Autodesk Fusion 360 part; units mm, degrees
(part 2 of 2)
sketch "Editable cross section (97)" plane through (0, 0, 0) normal (0, 0, 1) x (1, 0, 0) in component "left scoring bearing bridge -33"
  line L0 (-7.5, -5) -> (7.5, -5)
  line L1 (7.5, -5) -> (7.5, 5)
  line L2 (7.5, 5) -> (-7.5, 5)
  line L3 (-7.5, 5) -> (-7.5, -5)
extrude "Stock length''''''''''''''''''''''''''''''''''''''''''''''''''''''''''''''''''''''''''''''''''''''''''''''''" add sketch "Editable cross section (97)" along normal blind 42 separate body makes body 97 in component "left scoring bearing bridge -33"
sketch "Editable cross section (98)" plane through (0, 0, 0) normal (0, 0, 1) x (1, 0, 0) in component "left scoring bearing bridge 33"
  line L0 (-7.5, -5) -> (7.5, -5)
  line L1 (7.5, -5) -> (7.5, 5)
  line L2 (7.5, 5) -> (-7.5, 5)
  line L3 (-7.5, 5) -> (-7.5, -5)
extrude "Stock length'''''''''''''''''''''''''''''''''''''''''''''''''''''''''''''''''''''''''''''''''''''''''''''''''" add sketch "Editable cross section (98)" along normal blind 42 separate body makes body 98 in component "left scoring bearing bridge 33"
sketch "Editable cross section (99)" plane through (0, 0, 0) normal (0, 0, 1) x (1, 0, 0) in component "left feed diverter pivot"
  circle A0 centre (0, 0) radius 7
extrude "Stock length''''''''''''''''''''''''''''''''''''''''''''''''''''''''''''''''''''''''''''''''''''''''''''''''''" add sketch "Editable cross section (99)" along normal blind 24 separate body makes body 99 in component "left feed diverter pivot"
sketch "Editable cross section (100)" plane through (0, 0, 0) normal (0, 0, 1) x (1, 0, 0) in component "right feed diverter pivot"
  circle A0 centre (0, 0) radius 7
extrude "Stock length'''''''''''''''''''''''''''''''''''''''''''''''''''''''''''''''''''''''''''''''''''''''''''''''''''" add sketch "Editable cross section (100)" along normal blind 24 separate body makes body 100 in component "right feed diverter pivot"
sketch "Editable cross section (101)" plane through (0, 0, 0) normal (0, 0, 1) x (1, 0, 0) in component "feed diverter vane"
  line L0 (-2, -75) -> (2, -75)
  line L1 (2, -75) -> (2, 75)
  line L2 (2, 75) -> (-2, 75)
  line L3 (-2, 75) -> (-2, -75)
extrude "Stock length''''''''''''''''''''''''''''''''''''''''''''''''''''''''''''''''''''''''''''''''''''''''''''''''''''" add sketch "Editable cross section (101)" along normal blind 46 separate body makes body 101 in component "feed diverter vane"
sketch "Editable cross section (102)" plane through (0, 0, 0) normal (0, 0, 1) x (1, 0, 0) in component "front left public wheel"
  circle A0 centre (0, 0) radius 38.1
extrude "Stock length'''''''''''''''''''''''''''''''''''''''''''''''''''''''''''''''''''''''''''''''''''''''''''''''''''''" add sketch "Editable cross section (102)" along normal blind 26 separate body makes body 102 in component "front left public wheel"
sketch "Editable cross section (103)" plane through (0, 0, 0) normal (0, 0, 1) x (1, 0, 0) in component "front left public drive housing"
  line L0 (-40, -40) -> (40, -40)
  line L1 (40, -40) -> (40, 40)
  line L2 (40, 40) -> (-40, 40)
  line L3 (-40, 40) -> (-40, -40)
extrude "Stock length''''''''''''''''''''''''''''''''''''''''''''''''''''''''''''''''''''''''''''''''''''''''''''''''''''''" add sketch "Editable cross section (103)" along normal blind 45 separate body makes body 103 in component "front left public drive housing"
sketch "Editable cross section (104)" plane through (0, 0, 0) normal (0, 0, 1) x (1, 0, 0) in component "front left public motor reserve"
  circle A0 centre (0, 0) radius 29.9
extrude "Stock length'''''''''''''''''''''''''''''''''''''''''''''''''''''''''''''''''''''''''''''''''''''''''''''''''''''''" add sketch "Editable cross section (104)" along normal blind 56.46 separate body makes body 104 in component "front left public motor reserve"
sketch "Editable cross section (105)" plane through (0, 0, 0) normal (0, 0, 1) x (1, 0, 0) in component "front right public wheel"
  circle A0 centre (0, 0) radius 38.1
extrude "Stock length''''''''''''''''''''''''''''''''''''''''''''''''''''''''''''''''''''''''''''''''''''''''''''''''''''''''" add sketch "Editable cross section (105)" along normal blind 26 separate body makes body 105 in component "front right public wheel"
sketch "Editable cross section (106)" plane through (0, 0, 0) normal (0, 0, 1) x (1, 0, 0) in component "front right public drive housing"
  line L0 (-40, -40) -> (40, -40)
  line L1 (40, -40) -> (40, 40)
  line L2 (40, 40) -> (-40, 40)
  line L3 (-40, 40) -> (-40, -40)
extrude "Stock length'''''''''''''''''''''''''''''''''''''''''''''''''''''''''''''''''''''''''''''''''''''''''''''''''''''''''" add sketch "Editable cross section (106)" along normal blind 45 separate body makes body 106 in component "front right public drive housing"
sketch "Editable cross section (107)" plane through (0, 0, 0) normal (0, 0, 1) x (1, 0, 0) in component "front right public motor reserve"
  circle A0 centre (0, 0) radius 29.9
extrude "Stock length''''''''''''''''''''''''''''''''''''''''''''''''''''''''''''''''''''''''''''''''''''''''''''''''''''''''''" add sketch "Editable cross section (107)" along normal blind 56.46 separate body makes body 107 in component "front right public motor reserve"
sketch "Editable cross section (108)" plane through (0, 0, 0) normal (0, 0, 1) x (1, 0, 0) in component "rear left public wheel"
  circle A0 centre (0, 0) radius 38.1
extrude "Stock length'''''''''''''''''''''''''''''''''''''''''''''''''''''''''''''''''''''''''''''''''''''''''''''''''''''''''''" add sketch "Editable cross section (108)" along normal blind 26 separate body makes body 108 in component "rear left public wheel"
sketch "Editable cross section (109)" plane through (0, 0, 0) normal (0, 0, 1) x (1, 0, 0) in component "rear left public drive housing"
  line L0 (-40, -40) -> (40, -40)
  line L1 (40, -40) -> (40, 40)
  line L2 (40, 40) -> (-40, 40)
  line L3 (-40, 40) -> (-40, -40)
extrude "Stock length''''''''''''''''''''''''''''''''''''''''''''''''''''''''''''''''''''''''''''''''''''''''''''''''''''''''''''" add sketch "Editable cross section (109)" along normal blind 45 separate body makes body 109 in component "rear left public drive housing"
sketch "Editable cross section (110)" plane through (0, 0, 0) normal (0, 0, 1) x (1, 0, 0) in component "rear left public motor reserve"
  circle A0 centre (0, 0) radius 29.9
extrude "Stock length'''''''''''''''''''''''''''''''''''''''''''''''''''''''''''''''''''''''''''''''''''''''''''''''''''''''''''''" add sketch "Editable cross section (110)" along normal blind 56.46 separate body makes body 110 in component "rear left public motor reserve"
sketch "Editable cross section (111)" plane through (0, 0, 0) normal (0, 0, 1) x (1, 0, 0) in component "rear right public wheel"
  circle A0 centre (0, 0) radius 38.1
extrude "Stock length''''''''''''''''''''''''''''''''''''''''''''''''''''''''''''''''''''''''''''''''''''''''''''''''''''''''''''''" add sketch "Editable cross section (111)" along normal blind 26 separate body makes body 111 in component "rear right public wheel"
sketch "Editable cross section (112)" plane through (0, 0, 0) normal (0, 0, 1) x (1, 0, 0) in component "rear right public drive housing"
  line L0 (-40, -40) -> (40, -40)
  line L1 (40, -40) -> (40, 40)
  line L2 (40, 40) -> (-40, 40)
  line L3 (-40, 40) -> (-40, -40)
extrude "Stock length'''''''''''''''''''''''''''''''''''''''''''''''''''''''''''''''''''''''''''''''''''''''''''''''''''''''''''''''" add sketch "Editable cross section (112)" along normal blind 45 separate body makes body 112 in component "rear right public drive housing"
sketch "Editable cross section (113)" plane through (0, 0, 0) normal (0, 0, 1) x (1, 0, 0) in component "rear right public motor reserve"
  circle A0 centre (0, 0) radius 29.9
extrude "Stock length''''''''''''''''''''''''''''''''''''''''''''''''''''''''''''''''''''''''''''''''''''''''''''''''''''''''''''''''" add sketch "Editable cross section (113)" along normal blind 56.46 separate body makes body 113 in component "rear right public motor reserve"
sketch "Editable cross section (114)" plane through (0, 0, 0) normal (0, 0, 1) x (1, 0, 0) in component "right public scoring motor envelope"
  circle A0 centre (0, 0) radius 30
extrude "Stock length'''''''''''''''''''''''''''''''''''''''''''''''''''''''''''''''''''''''''''''''''''''''''''''''''''''''''''''''''" add sketch "Editable cross section (114)" along normal blind 93.26 separate body makes body 114 in component "right public scoring motor envelope"
sketch "Editable cross section (115)" plane through (0, 0, 0) normal (0, 0, 1) x (1, 0, 0) in component "left public scoring motor envelope"
  circle A0 centre (0, 0) radius 30
extrude "Stock length''''''''''''''''''''''''''''''''''''''''''''''''''''''''''''''''''''''''''''''''''''''''''''''''''''''''''''''''''" add sketch "Editable cross section (115)" along normal blind 93.26 separate body makes body 115 in component "left public scoring motor envelope"
sketch "Editable cross section (116)" plane through (0, 0, 0) normal (0, 0, 1) x (1, 0, 0) in component "rear lift custody gate"
  line L0 (-2, -65) -> (2, -65)
  line L1 (2, -65) -> (2, 65)
  line L2 (2, 65) -> (-2, 65)
  line L3 (-2, 65) -> (-2, -65)
extrude "Stock length'''''''''''''''''''''''''''''''''''''''''''''''''''''''''''''''''''''''''''''''''''''''''''''''''''''''''''''''''''" add sketch "Editable cross section (116)" along normal blind 416 separate body makes body 116 in component "rear lift custody gate"
sketch "Editable cross section (117)" plane through (0, 0, 0) normal (0, 0, 1) x (1, 0, 0) in component "front lift custody guide"
  line L0 (-2, -65) -> (2, -65)
  line L1 (2, -65) -> (2, 65)
  line L2 (2, 65) -> (-2, 65)
  line L3 (-2, 65) -> (-2, -65)
extrude "Stock length''''''''''''''''''''''''''''''''''''''''''''''''''''''''''''''''''''''''''''''''''''''''''''''''''''''''''''''''''''" add sketch "Editable cross section (117)" along normal blind 361 separate body makes body 117 in component "front lift custody guide"
component "left perimeter tube" placed x (0, 1, 0) y (0, 0, 1) z (1, 0, 0) at (-340, 327.3, 89.4)
component "left front return" placed x (-1, 0, 0) y (0, 0, 1) z (0, 1, 0) at (327.3, 150, 89.4)
component "left blue side bumper" placed x (1, 0, 0) y (0, 1, 0) z (0, 0, 1) at (0, 378, 48)
component "left blue front bumper" placed x (1, 0, 0) y (0, 1, 0) z (0, 0, 1) at (378, 245, 48)
component "right perimeter tube" placed x (0, 1, 0) y (0, 0, 1) z (1, 0, 0) at (-340, -327.3, 89.4)
component "right front return" placed x (-1, 0, 0) y (0, 0, 1) z (0, 1, 0) at (327.3, -314.6, 89.4)
component "right blue side bumper" placed x (1, 0, 0) y (0, 1, 0) z (0, 0, 1) at (0, -378, 48)
component "right blue front bumper" placed x (1, 0, 0) y (0, 1, 0) z (0, 0, 1) at (378, -245, 48)
component "rear perimeter tube" placed x (-1, 0, 0) y (0, 0, 1) z (0, 1, 0) at (-327.3, -314.6, 89.4)
component "rear blue bumper" placed x (1, 0, 0) y (0, 1, 0) z (0, 0, 1) at (-378, 0, 48)
component "front left module tab spacer 1" placed x (1, 0, 0) y (0, 1, 0) z (0, 0, 1) at (198, 303.05, 78.32)
component "front left module tab spacer 2" placed x (1, 0, 0) y (0, 1, 0) z (0, 0, 1) at (303.05, 198, 78.32)
component "front right module tab spacer 1" placed x (1, 0, 0) y (0, 1, 0) z (0, 0, 1) at (303.05, -198, 78.32)
component "front right module tab spacer 2" placed x (1, 0, 0) y (0, 1, 0) z (0, 0, 1) at (198, -303.05, 78.32)
component "rear left module tab spacer 1" placed x (1, 0, 0) y (0, 1, 0) z (0, 0, 1) at (-303.05, 198, 78.32)
component "rear left module tab spacer 2" placed x (1, 0, 0) y (0, 1, 0) z (0, 0, 1) at (-198, 303.05, 78.32)
component "rear right module tab spacer 1" placed x (1, 0, 0) y (0, 1, 0) z (0, 0, 1) at (-198, -303.05, 78.32)
component "rear right module tab spacer 2" placed x (1, 0, 0) y (0, 1, 0) z (0, 0, 1) at (-303.05, -198, 78.32)
component "rear right hopper post" placed x (1, 0, 0) y (0, 1, 0) z (0, 0, 1) at (-188, -306, 115)
component "front right hopper post" placed x (1, 0, 0) y (0, 1, 0) z (0, 0, 1) at (176, -306, 115)
component "right floor sill" placed x (0, 1, 0) y (0, 0, 1) z (1, 0, 0) at (-330, -306, 227)
component "rear left hopper post" placed x (1, 0, 0) y (0, 1, 0) z (0, 0, 1) at (-188, 306, 115)
component "front left hopper post" placed x (1, 0, 0) y (0, 1, 0) z (0, 0, 1) at (176, 306, 115)
component "left floor sill" placed x (0, 1, 0) y (0, 0, 1) z (1, 0, 0) at (-330, 306, 227)
component "rear deck crossmember" placed x (-1, 0, 0) y (0, 0, 1) z (0, 1, 0) at (-188, -315, 113)
component "front deck crossmember" placed x (-1, 0, 0) y (0, 0, 1) z (0, 1, 0) at (176, -315, 113)
component "left electronics deck" placed x (1, 0, 0) y (0, 1, 0) z (0, 0, 1) at (-5.5, 149, 122)
component "right electronics deck" placed x (1, 0, 0) y (0, 1, 0) z (0, 0, 1) at (-5.5, -147.5, 122)
component "fore electronics deck bridge" placed x (1, 0, 0) y (0, 1, 0) z (0, 0, 1) at (110.5, 1.5, 122)
component "aft electronics deck bridge" placed x (1, 0, 0) y (0, 1, 0) z (0, 0, 1) at (-157.5, 1.5, 122)
component "battery cradle floor" placed x (1, 0, 0) y (0, 1, 0) z (0, 0, 1) at (-41.5, 1.5, 44)
component "battery cradle wall -44" placed x (1, 0, 0) y (0, 1, 0) z (0, 0, 1) at (-41.5, -42, 48)
component "battery cradle wall 43" placed x (1, 0, 0) y (0, 1, 0) z (0, 0, 1) at (-41.5, 45, 48)
component "battery secured envelope" placed x (1, 0, 0) y (0, 1, 0) z (0, 0, 1) at (-41.5, 2, 48)
component "distribution enclosure reserve" placed x (1, 0, 0) y (0, 1, 0) z (0, 0, 1) at (105, -3, 129)
component "robot controller reserve" placed x (1, 0, 0) y (0, 1, 0) z (0, 0, 1) at (-79.5, 108, 129)
component "field radio reserve" placed x (1, 0, 0) y (0, 1, 0) z (0, 0, 1) at (-88.5, -118.5, 129)
component "drive controller reserve 1" placed x (1, 0, 0) y (0, 1, 0) z (0, 0, 1) at (-120.5, -204, 129)
component "drive controller reserve 2" placed x (1, 0, 0) y (0, 1, 0) z (0, 0, 1) at (-120.5, 204, 129)
component "drive controller reserve 3" placed x (1, 0, 0) y (0, 1, 0) z (0, 0, 1) at (-42.5, -204, 129)
component "drive controller reserve 4" placed x (1, 0, 0) y (0, 1, 0) z (0, 0, 1) at (-42.5, 204, 129)
component "drive controller reserve 5" placed x (1, 0, 0) y (0, 1, 0) z (0, 0, 1) at (35.5, -204, 129)
component "drive controller reserve 6" placed x (1, 0, 0) y (0, 1, 0) z (0, 0, 1) at (35.5, 204, 129)
component "drive controller reserve 7" placed x (1, 0, 0) y (0, 1, 0) z (0, 0, 1) at (113.5, -204, 129)
component "drive controller reserve 8" placed x (1, 0, 0) y (0, 1, 0) z (0, 0, 1) at (113.5, 204, 129)
component "hopper back panel" placed x (1, 0, 0) y (0, 1, 0) z (0, 0, 1) at (-332, 0, 232)
component "right hopper wall" placed x (1, 0, 0) y (0, 1, 0) z (0, 0, 1) at (-91, -313, 232)
component "right hopper front wing" placed x (1, 0, 0) y (0, 1, 0) z (0, 0, 1) at (150, -199, 232)
component "right cross feed deck" placed x (1, 0, 0) y (0, 1, 0) z (0, 0, 1) at (-91, -199, 230)
component "right front elevator upright" placed x (1, 0, 0) y (0, 1, 0) z (0, 0, 1) at (183, -105, 111)
component "right rear elevator upright" placed x (1, 0, 0) y (0, 1, 0) z (0, 0, 1) at (319, -105, 113)
component "right elevator upper tie" placed x (0, 1, 0) y (0, 0, 1) z (1, 0, 0) at (181, -105, 637)
component "right inside lift belt" placed x (1, 0, 0) y (0, 1, 0) z (0, 0, 1) at (196, -91, 86)
component "right outside lift belt" placed x (1, 0, 0) y (0, 1, 0) z (0, 0, 1) at (301, -91, 86)
component "right lift shelf 1" placed x (1, 0, 0) y (0, 1, 0) z (0, 0, 1) at (244, -81, 99)
component "right lift shelf 2" placed x (1, 0, 0) y (0, 1, 0) z (0, 0, 1) at (244, -81, 258)
component "right lift shelf 3" placed x (1, 0, 0) y (0, 1, 0) z (0, 0, 1) at (244, -81, 417)
component "right lift shelf 4" placed x (1, 0, 0) y (0, 1, 0) z (0, 0, 1) at (244, -81, 576)
component "right intake ramp" placed x (0, 1, 0) y (0.257178, 0, 0.966364) z (0.966364, 0, -0.257178) at (213, -60, 48)
component "left hopper wall" placed x (1, 0, 0) y (0, 1, 0) z (0, 0, 1) at (-91, 313, 232)
component "left hopper front wing" placed x (1, 0, 0) y (0, 1, 0) z (0, 0, 1) at (150, 199, 232)
component "left cross feed deck" placed x (1, 0, 0) y (0, 1, 0) z (0, 0, 1) at (-91, 199, 230)
component "left front elevator upright" placed x (1, 0, 0) y (0, 1, 0) z (0, 0, 1) at (183, 105, 111)
component "left rear elevator upright" placed x (1, 0, 0) y (0, 1, 0) z (0, 0, 1) at (319, 105, 113)
component "left elevator upper tie" placed x (0, 1, 0) y (0, 0, 1) z (1, 0, 0) at (181, 105, 637)
component "left inside lift belt" placed x (1, 0, 0) y (0, 1, 0) z (0, 0, 1) at (196, 91, 86)
component "left outside lift belt" placed x (1, 0, 0) y (0, 1, 0) z (0, 0, 1) at (301, 91, 86)
component "left lift shelf 1" placed x (1, 0, 0) y (0, 1, 0) z (0, 0, 1) at (244, 81, 99)
component "left lift shelf 2" placed x (1, 0, 0) y (0, 1, 0) z (0, 0, 1) at (244, 81, 258)
component "left lift shelf 3" placed x (1, 0, 0) y (0, 1, 0) z (0, 0, 1) at (244, 81, 417)
component "left lift shelf 4" placed x (1, 0, 0) y (0, 1, 0) z (0, 0, 1) at (244, 81, 576)
component "left intake ramp" placed x (0, 1, 0) y (0.257178, 0, 0.966364) z (0.966364, 0, -0.257178) at (213, 60, 48)
component "central fore-aft feed deck" placed x (1, 0, 0) y (0, 1, 0) z (0, 0, 1) at (-90.5, 0, 230)
component "left lower lift stub shaft" placed x (-1, 0, 0) y (0, 0, 1) z (0, 1, 0) at (248, 88, 84)
component "right lower lift stub shaft" placed x (-1, 0, 0) y (0, 0, 1) z (0, 1, 0) at (248, -116, 84)
component "left upper lift stub shaft" placed x (-1, 0, 0) y (0, 0, 1) z (0, 1, 0) at (248, 88, 622)
component "right upper lift stub shaft" placed x (-1, 0, 0) y (0, 0, 1) z (0, 1, 0) at (248, -116, 622)
component "ground intake roller" placed x (-1, 0, 0) y (0, 0, 1) z (0, 1, 0) at (285.7664, -126, 342.4358)
component "right intake bearing arm" placed x (0.994522, 0, -0.104528) y (0, 1, 0) z (0.104528, 0, 0.994522) at (275, -150, 240)
component "right intake pivot plate" placed x (0, -1, 0) y (-0.17238, 0, 0.98503) z (-0.98503, 0, -0.17238) at (315, -150, 247)
component "right intake pivot axle" placed x (-1, 0, 0) y (0, 0, 1) z (0, 1, 0) at (275, -150, 240)
component "right intake journal" placed x (-1, 0, 0) y (0, 0, 1) z (0, 1, 0) at (285.7664, -150, 342.4358)
component "right upper head cheek" placed x (1, 0, 0) y (0, 1, 0) z (0, 0, 1) at (236, -150, 562)
component "left intake bearing arm" placed x (0.994522, 0, -0.104528) y (0, 1, 0) z (0.104528, 0, 0.994522) at (275, 150, 240)
component "left intake pivot plate" placed x (0, -1, 0) y (-0.17238, 0, 0.98503) z (-0.98503, 0, -0.17238) at (315, 150, 247)
component "left intake pivot axle" placed x (-1, 0, 0) y (0, 0, 1) z (0, 1, 0) at (275, 100, 240)
component "left intake journal" placed x (-1, 0, 0) y (0, 0, 1) z (0, 1, 0) at (285.7664, 126, 342.4358)
component "left upper head cheek" placed x (1, 0, 0) y (0, 1, 0) z (0, 0, 1) at (236, 150, 562)
component "right scoring wheel" placed x (0, -1, 0) y (0.5, 0, 0.866025) z (-0.866025, 0, 0.5) at (259.6506, -104, 588.5)
component "right scoring spindle" placed x (0, -1, 0) y (0.5, 0, 0.866025) z (-0.866025, 0, 0.5) at (269.1769, -104, 583)
component "right upper guide" placed x (0, 1, 0) y (-0.841019, 0, 0.541006) z (0.541006, 0, 0.841019) at (190, -80, 548)
component "right scoring bearing bridge -33" placed x (-1, 0, 0) y (0, 0, 1) z (0, 1, 0) at (266.5788, -146, 584.5)
component "right scoring bearing bridge 33" placed x (-1, 0, 0) y (0, 0, 1) z (0, 1, 0) at (209.4212, -146, 617.5)
component "left scoring wheel" placed x (0, -1, 0) y (0.5, 0, 0.866025) z (-0.866025, 0, 0.5) at (259.6506, 104, 588.5)
component "left scoring spindle" placed x (0, -1, 0) y (0.5, 0, 0.866025) z (-0.866025, 0, 0.5) at (269.1769, 104, 583)
component "left upper guide" placed x (0, 1, 0) y (-0.841019, 0, 0.541006) z (0.541006, 0, 0.841019) at (190, 80, 548)
component "left scoring bearing bridge -33" placed x (-1, 0, 0) y (0, 0, 1) z (0, 1, 0) at (266.5788, 104, 584.5)
component "left scoring bearing bridge 33" placed x (-1, 0, 0) y (0, 0, 1) z (0, 1, 0) at (209.4212, 104, 617.5)
component "left feed diverter pivot" placed x (-1, 0, 0) y (0, 0, 1) z (0, 1, 0) at (156, 76, 548)
component "right feed diverter pivot" placed x (-1, 0, 0) y (0, 0, 1) z (0, 1, 0) at (156, -100, 548)
component "feed diverter vane" placed x (1, 0, 0) y (0, 1, 0) z (0, 0, 1) at (156, 0, 548)
component "front left public wheel" placed x (-1, 0, 0) y (0, 0, 1) z (0, 1, 0) at (268, 255, 38.1)
component "front left public drive housing" placed x (1, 0, 0) y (0, 1, 0) z (0, 0, 1) at (268, 268, 70)
component "front left public motor reserve" placed x (1, 0, 0) y (0, 1, 0) z (0, 0, 1) at (268, 268, 115)
component "front right public wheel" placed x (-1, 0, 0) y (0, 0, 1) z (0, 1, 0) at (268, -281, 38.1)
component "front right public drive housing" placed x (1, 0, 0) y (0, 1, 0) z (0, 0, 1) at (268, -268, 70)
component "front right public motor reserve" placed x (1, 0, 0) y (0, 1, 0) z (0, 0, 1) at (268, -268, 115)
component "rear left public wheel" placed x (-1, 0, 0) y (0, 0, 1) z (0, 1, 0) at (-268, 255, 38.1)
component "rear left public drive housing" placed x (1, 0, 0) y (0, 1, 0) z (0, 0, 1) at (-268, 268, 70)
component "rear left public motor reserve" placed x (1, 0, 0) y (0, 1, 0) z (0, 0, 1) at (-268, 268, 115)
component "rear right public wheel" placed x (-1, 0, 0) y (0, 0, 1) z (0, 1, 0) at (-268, -281, 38.1)
component "rear right public drive housing" placed x (1, 0, 0) y (0, 1, 0) z (0, 0, 1) at (-268, -268, 70)
component "rear right public motor reserve" placed x (1, 0, 0) y (0, 1, 0) z (0, 0, 1) at (-268, -268, 115)
component "right public scoring motor envelope" placed x (0, -1, 0) y (0.5, 0, 0.866025) z (-0.866025, 0, 0.5) at (213.7513, -104, 615)
component "left public scoring motor envelope" placed x (0, -1, 0) y (0.5, 0, 0.866025) z (-0.866025, 0, 0.5) at (213.7513, 104, 615)
component "rear lift custody gate" placed x (1, 0, 0) y (0, 1, 0) z (0, 0, 1) at (169, 0, 134)
component "front lift custody guide" placed x (1, 0, 0) y (0, 1, 0) z (0, 0, 1) at (329, 0, 221)
named bodies: "left perimeter tube", "left front return", "left blue side bumper", "left blue front bumper", "right perimeter tube", "right front return", "right blue side bumper", "right blue front bumper", "rear perimeter tube", "rear blue bumper", "front left module tab spacer 1", "front left module tab spacer 2", "front right module tab spacer 1", "front right module tab spacer 2", "rear left module tab spacer 1", "rear left module tab spacer 2", "rear right module tab spacer 1", "rear right module tab spacer 2", "rear right hopper post", "front right hopper post", "right floor sill", "rear left hopper post", "front left hopper post", "left floor sill", "rear deck crossmember", "front deck crossmember", "left electronics deck", "right electronics deck", "fore electronics deck bridge", "aft electronics deck bridge", "battery cradle floor", "battery cradle wall -44", "battery cradle wall 43", "battery secured envelope", "distribution enclosure reserve", "robot controller reserve", "field radio reserve", "drive controller reserve 1", "drive controller reserve 2", "drive controller reserve 3", "drive controller reserve 4", "drive controller reserve 5", "drive controller reserve 6", "drive controller reserve 7", "drive controller reserve 8", "hopper back panel", "right hopper wall", "right hopper front wing", "right cross feed deck", "right front elevator upright", "right rear elevator upright", "right elevator upper tie", "right inside lift belt", "right outside lift belt", "right lift shelf 1", "right lift shelf 2", "right lift shelf 3", "right lift shelf 4", "right intake ramp", "left hopper wall", "left hopper front wing", "left cross feed deck", "left front elevator upright", "left rear elevator upright", "left elevator upper tie", "left inside lift belt", "left outside lift belt", "left lift shelf 1", "left lift shelf 2", "left lift shelf 3", "left lift shelf 4", "left intake ramp", "central fore-aft feed deck", "left lower lift stub shaft", "right lower lift stub shaft", "left upper lift stub shaft", "right upper lift stub shaft", "ground intake roller", "right intake bearing arm", "right intake pivot plate", "right intake pivot axle", "right intake journal", "right upper head cheek", "left intake bearing arm", "left intake pivot plate", "left intake pivot axle", "left intake journal", "left upper head cheek", "right scoring wheel", "right scoring spindle", "right upper guide", "right scoring bearing bridge -33", "right scoring bearing bridge 33", "left scoring wheel", "left scoring spindle", "left upper guide", "left scoring bearing bridge -33", "left scoring bearing bridge 33", "left feed diverter pivot", "right feed diverter pivot", "feed diverter vane", "front left public wheel", "front left public drive housing", "front left public motor reserve", "front right public wheel", "front right public drive housing", "front right public motor reserve", "rear left public wheel", "rear left public drive housing", "rear left public motor reserve", "rear right public wheel", "rear right public drive housing", "rear right public motor reserve", "right public scoring motor envelope", "left public scoring motor envelope", "rear lift custody gate", "front lift custody guide"
